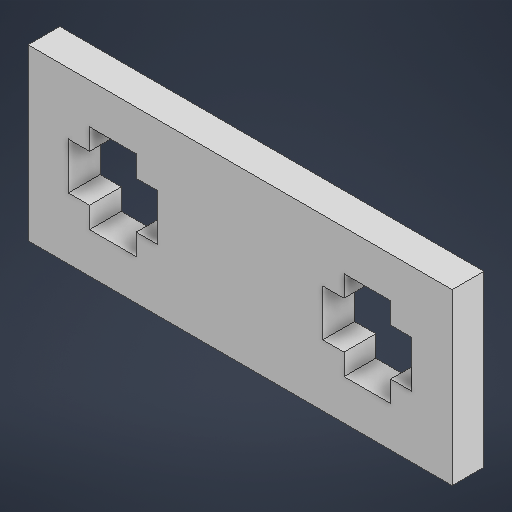
# Autodesk Inventor part: ŞASE
Saved by Autodesk Inventor 2026.1 (Build 301233020, 233B)
## iProperties
Created: 2026-04-08
Part Number: ŞASE
Material: Generic
Document SubType Name: Modeling
Designer: kadir
Density: 1 g/cm^3
Appearance: Default
Author: kadir
Autodesk Inventor part; units mm, degrees
ref_plane "YZ Plane" through (0, 0, 0) normal (1, 0, 0) x (0, 1, 0)
ref_plane "XZ Plane" through (0, 0, 0) normal (0, 1, 0) x (-1, 0, 0)
ref_plane "XY Plane" through (0, 0, 0) normal (0, 0, 1) x (1, 0, 0)
sketch "Sketch1" plane through (0, 0, 0) normal (0, 0, 1) x (1, 0, 0)
  line L0 (100, 40) -> (-100, 40)
  line L1 (-100, 40) -> (-100, -40)
  line L2 (-100, -40) -> (100, -40)
  line L3 (100, -40) -> (100, 40)
  line L4 (100, 40) -> (-100, -40) construction
  line L5 (-100, 40) -> (100, -40) construction
  line L6 (-49, 21) -> (-71, 21)
  line L7 (-71, 21) -> (-71, -21)
  line L8 (-71, -21) -> (-49, -21)
  line L9 (-49, -21) -> (-49, 21)
  line L10 (-49, 21) -> (-71, -21) construction
  line L11 (-71, 21) -> (-49, -21) construction
  line L12 (0, 40) -> (0, -40)
  line L13 (49, 21) -> (71, 21)
  line L14 (71, 21) -> (71, -21)
  line L15 (71, -21) -> (49, -21)
  line L16 (49, -21) -> (49, 21)
  line L17 (49, 21) -> (71, -21) construction
  line L18 (71, 21) -> (49, -21) construction
  line L19 (-39, 11) -> (-81, 11)
  line L20 (-81, 11) -> (-81, -11)
  line L21 (-81, -11) -> (-39, -11)
  line L22 (-39, -11) -> (-39, 11)
  line L23 (-39, 11) -> (-81, -11) construction
  line L24 (-81, 11) -> (-39, -11) construction
  line L25 (39, 11) -> (81, 11)
  line L26 (81, 11) -> (81, -11)
  line L27 (81, -11) -> (39, -11)
  line L28 (39, -11) -> (39, 11)
  line L29 (39, 11) -> (81, -11) construction
  line L30 (81, 11) -> (39, -11) construction
  point P0 (0, 0)
  point P1 (-60, 0)
  point P2 (60, 0)
  point P3 (71, 11)
  point P4 (71, -11)
  point P5 (49, -11)
  point P6 (49, 11)
  point P7 (-49, 11)
  point P8 (-49, -11)
  point P9 (-71, -11)
  point P10 (-71, 11)
  dimension "d0" = 200
  dimension "d1" = 80
  dimension "d2" = 22
  dimension "d3" = 42
  dimension "d4" = 120
  dimension "d5" = 42
  dimension "d6" = 22
  constraints: 62 end point, 9 symmetric about line, 8 midpoint, 6 parallel, 3 horizontal, 3 perpendicular, 1 horizontal alignment
  measures "d0" distance of L2.end L1.end
  measures "d1" distance of L0.end L1.end
  measures "d2" distance of L8.end L7.end
  measures "d3" distance of L7.end L6.end
  measures "d4" diameter of point (-60, 0) L12
  measures "d5" distance of L21.end L20.end
  measures "d6" distance of L20.end L19.end
extrude "Extrusion1" add sketch "Sketch1" along normal blind 15
body "Solid1"
